Autodesk Fusion 360 part; units mm, degrees
(part 3 of 3)
extrude "Extrude8" add sketch "Sketch8" along normal blind -6.35 and the other way blind 2.54 contours L0 L1 L15 L16 | L1 L3 L15 L16 | L3 A8 L12 L13 L14 L15 L16 | L3 L16 L17 | A8 | A6 A8 L10 L11 | A6
extrude "Extrude9" add sketch "Sketch8" against normal blind 2.54 contours L0 L1 L15 L16 | A8 | A6
sketch "Sketch9" plane through (6.35, 0, 0) normal (1, 0, 0) x (0, 1, 0)
  circle A0 centre (25.4, 0) radius 2.1971
  circle A1 centre (0, 0) radius 2.1971
  circle A2 centre (-12.7, 1.5875) radius 1.6
  circle A3 centre (-63.5, 1.5875) radius 1.6
  line L0 (-90.805, 4.7625) -> (-90.805, -4.7625)
  line L1 (-90.805, -4.7625) -> (31.75, -4.7625)
  line L2 (31.75, -4.7625) -> (31.75, 4.7625)
  line L3 (31.75, 4.7625) -> (-90.805, 4.7625)
  line L4 (17.4625, -1.5875) -> (17.4625, -4.7625)
  line L5 (17.4625, -4.7625) -> (7.9375, -4.7625)
  line L6 (7.9375, -4.7625) -> (7.9375, -1.5875)
  line L7 (7.9375, -1.5875) -> (17.4625, -1.5875)
  line L8 (0, -2.1971) -> (7.9375, -2.1971)
  dimension "d55" = 9.525
  dimension "d56" = 3.175
  dimension "d57" = 7.9375
  constraint vertical L4
  constraint horizontal L5
  constraint vertical L6
  constraint perpendicular L4 L7
  constraint collinear L1 L5
  constraint coincident A1 L8.start
  constraint coincident L6 L8.end
  constraint tangent A1 L8
  constraint perpendicular L6 L8
  measures "d55" distance of L6.end L4.start
  measures "d56" distance of L4.end L4.start
  measures "d57" distance of L8.start L8.end
extrude "Extrude10" [suppressed]
extrude "Extrude11" [suppressed]
equation "d7 = 0.5 in - ( 0.2 / 2 ) * 1 in"
equation "d10 = ( 0.375 / 2 ) * 1 in"
equation "d11 = ( ( 1.5 - 1 ) / 2 ) * 1 in"
equation "d39 = 0.263 in + 0.125 in"
